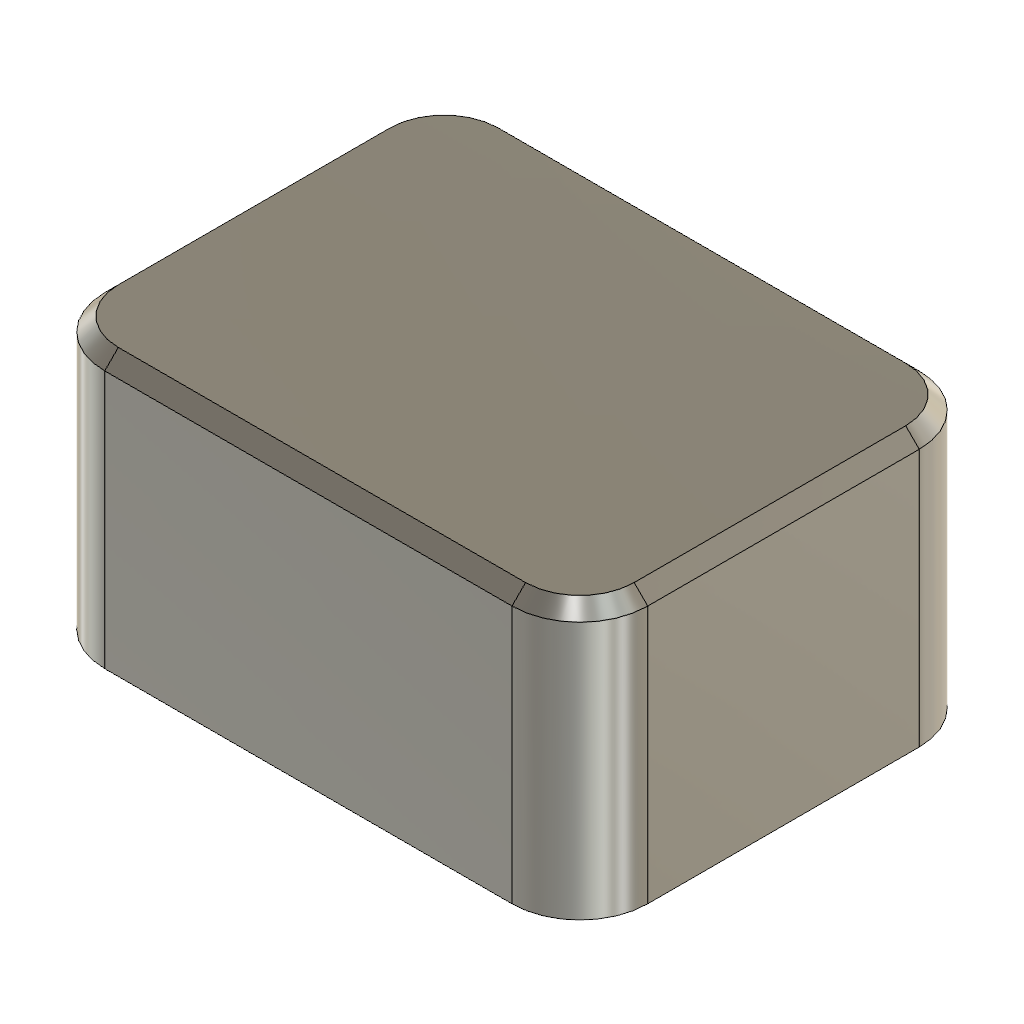
vendor_BevelRimChain (Autodesk Fusion 360 design; units mm, degrees)
Autodesk Fusion 360 part; units mm, degrees
sketch "Base sketch" plane through (0, 0, 0) normal (0, 0, 1) x (1, 0, 0)
  line L0 (0, 0) -> (40, 0)
  line L1 (40, 0) -> (40, 30)
  line L2 (40, 30) -> (0, 30)
  line L3 (0, 30) -> (0, 0)
extrude "Base extrude" add sketch "Base sketch" along normal blind 20
fillet "Corner rounds" radius 5 4 edges at (40, 30, 10) (0, 0, 10) (40, 0, 10) (0, 30, 10)
chamfer "Top bevel chain" distance 1 angle 45 8 edges at (20, 0, 20) (38.5355, 1.4645, 20) (40, 15, 20) (38.5355, 28.5355, 20) (20, 30, 20) (1.4645, 28.5355, 20) (0, 15, 20) (1.4645, 1.4645, 20) tangent chain off
equation "height = 20.0 mm"
